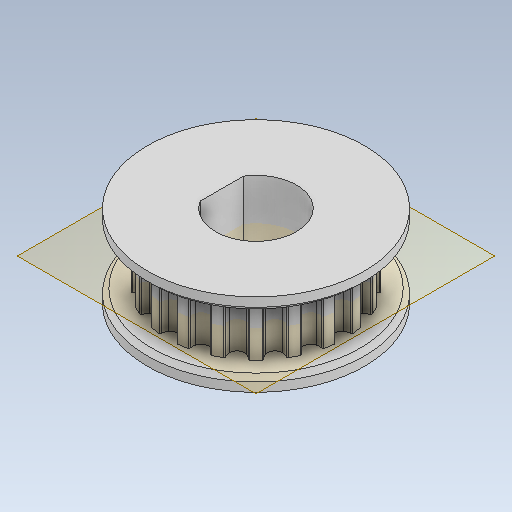
# Autodesk Inventor part: HTD-3M_20-Zähne
Saved by Autodesk Inventor 2026.4 (Build 304435030, 435C)
## iProperties
Created: 2026-11-19
Part Number: HTD-3M_20-Zähne
Material: Generisch
Document SubType Name: Modeling
Designer: weira
Density: 1 g/cm^3
Appearance: Vorgabe
Author: weira
Autodesk Inventor part; units mm, degrees
ref_plane "YZ Plane" through (0, 0, 0) normal (1, 0, 0) x (0, 1, 0)
ref_plane "XZ Plane" through (0, 0, 0) normal (0, 1, 0) x (-1, 0, 0)
sketch "Skizze1" plane through (0, 0, 0) normal (0, 0, 1) x (1, 0, 0)
  circle A0 centre (0, 0) radius 9.5511 construction
  line L0 (-5.6581, 20.033) -> (2.8903, 20.033)
  line L1 (2.8903, 20.033) -> (2.8903, 11.5277)
  line L2 (2.8903, 11.5277) -> (-5.6581, 11.5277)
  line L3 (-5.6581, 11.5277) -> (-5.6581, 20.033)
  circle A1 centre (0, 0) radius 8.6811 construction
  circle A2 centre (0, 0) radius 9.8211
  arc A3 (0.7095, 9.0476) -> (0.9041, 9.6681) centre (-0.61, 9.8021) ccw
  arc A4 (1.0279, 9.7672) -> (0.9041, 9.6681) centre (1.0264, 9.6422) ccw
  line L4 (0, 8.6811) -> (0, 7.1512) construction
  arc A5 (-0.9041, 9.6681) -> (-0.7095, 9.0476) centre (0.61, 9.8021) ccw
  arc A6 (-0.9041, 9.6681) -> (-1.0279, 9.7672) centre (-1.0264, 9.6422) ccw
  arc A7 (-0.7095, 9.0476) -> (0.7095, 9.0476) centre (0, 9.5511) ccw
  arc A8 (-2.0407, 9.6068) -> (-2.1278, 9.4743) centre (-2.0035, 9.4874) ccw
  arc A9 (-3.8474, 8.9155) -> (-3.9958, 8.9715) centre (-3.9557, 8.8531) ccw
  arc A10 (-2.1211, 8.824) -> (-2.1278, 9.4743) centre (-3.6092, 9.1339) ccw
  arc A11 (-3.8474, 8.9155) -> (-3.4706, 8.3855) centre (-2.4489, 9.5109) ccw
  arc A12 (-3.4706, 8.3855) -> (-2.1211, 8.824) centre (-2.9515, 9.0836) ccw
  arc A13 (-4.9094, 8.506) -> (-4.9513, 8.353) centre (-4.8372, 8.404) ccw
  arc A14 (-6.4142, 7.2902) -> (-6.5726, 7.2976) centre (-6.4979, 7.1974) ccw
  arc A15 (-4.744, 7.7367) -> (-4.9513, 8.353) centre (-6.2551, 7.5715) ccw
  arc A16 (-6.4142, 7.2902) -> (-5.892, 6.9026) centre (-5.2681, 8.2886) ccw
  arc A17 (-5.892, 6.9026) -> (-4.744, 7.7367) centre (-5.614, 7.727) ccw
  arc A18 (-7.2976, 6.5726) -> (-7.2902, 6.4142) centre (-7.1974, 6.4979) ccw
  arc A19 (-8.353, 4.9513) -> (-8.506, 4.9094) centre (-8.404, 4.8372) ccw
  arc A20 (-6.9026, 5.892) -> (-7.2902, 6.4142) centre (-8.2886, 5.2681) ccw
  arc A21 (-8.353, 4.9513) -> (-7.7367, 4.744) centre (-7.5715, 6.2551) ccw
  arc A22 (-7.7367, 4.744) -> (-6.9026, 5.892) centre (-7.727, 5.614) ccw
  arc A23 (-8.9715, 3.9958) -> (-8.9155, 3.8474) centre (-8.8531, 3.9557) ccw
  arc A24 (-9.4743, 2.1278) -> (-9.6068, 2.0407) centre (-9.4874, 2.0035) ccw
  arc A25 (-8.3855, 3.4706) -> (-8.9155, 3.8474) centre (-9.5109, 2.4489) ccw
  arc A26 (-9.4743, 2.1278) -> (-8.824, 2.1211) centre (-9.1339, 3.6092) ccw
  arc A27 (-8.824, 2.1211) -> (-8.3855, 3.4706) centre (-9.0836, 2.9515) ccw
  arc A28 (-9.7672, 1.0279) -> (-9.6681, 0.9041) centre (-9.6422, 1.0264) ccw
  arc A29 (-9.6681, -0.9041) -> (-9.7672, -1.0279) centre (-9.6422, -1.0264) ccw
  arc A30 (-9.0476, 0.7095) -> (-9.6681, 0.9041) centre (-9.8021, -0.61) ccw
  arc A31 (-9.6681, -0.9041) -> (-9.0476, -0.7095) centre (-9.8021, 0.61) ccw
  arc A32 (-9.0476, -0.7095) -> (-9.0476, 0.7095) centre (-9.5511, 0) ccw
  arc A33 (-9.6068, -2.0407) -> (-9.4743, -2.1278) centre (-9.4874, -2.0035) ccw
  arc A34 (-8.9155, -3.8474) -> (-8.9715, -3.9958) centre (-8.8531, -3.9557) ccw
  arc A35 (-8.824, -2.1211) -> (-9.4743, -2.1278) centre (-9.1339, -3.6092) ccw
  arc A36 (-8.9155, -3.8474) -> (-8.3855, -3.4706) centre (-9.5109, -2.4489) ccw
  arc A37 (-8.3855, -3.4706) -> (-8.824, -2.1211) centre (-9.0836, -2.9515) ccw
  arc A38 (-8.506, -4.9094) -> (-8.353, -4.9513) centre (-8.404, -4.8372) ccw
  arc A39 (-7.2902, -6.4142) -> (-7.2976, -6.5726) centre (-7.1974, -6.4979) ccw
  arc A40 (-7.7367, -4.744) -> (-8.353, -4.9513) centre (-7.5715, -6.2551) ccw
  arc A41 (-7.2902, -6.4142) -> (-6.9026, -5.892) centre (-8.2886, -5.2681) ccw
  arc A42 (-6.9026, -5.892) -> (-7.7367, -4.744) centre (-7.727, -5.614) ccw
  arc A43 (-6.5726, -7.2976) -> (-6.4142, -7.2902) centre (-6.4979, -7.1974) ccw
  arc A44 (-4.9513, -8.353) -> (-4.9094, -8.506) centre (-4.8372, -8.404) ccw
  arc A45 (-5.892, -6.9026) -> (-6.4142, -7.2902) centre (-5.2681, -8.2886) ccw
  arc A46 (-4.9513, -8.353) -> (-4.744, -7.7367) centre (-6.2551, -7.5715) ccw
  arc A47 (-4.744, -7.7367) -> (-5.892, -6.9026) centre (-5.614, -7.727) ccw
  arc A48 (-3.9958, -8.9715) -> (-3.8474, -8.9155) centre (-3.9557, -8.8531) ccw
  arc A49 (-2.1278, -9.4743) -> (-2.0407, -9.6068) centre (-2.0035, -9.4874) ccw
  arc A50 (-3.4706, -8.3855) -> (-3.8474, -8.9155) centre (-2.4489, -9.5109) ccw
  arc A51 (-2.1278, -9.4743) -> (-2.1211, -8.824) centre (-3.6092, -9.1339) ccw
  arc A52 (-2.1211, -8.824) -> (-3.4706, -8.3855) centre (-2.9515, -9.0836) ccw
  arc A53 (-1.0279, -9.7672) -> (-0.9041, -9.6681) centre (-1.0264, -9.6422) ccw
  arc A54 (0.9041, -9.6681) -> (1.0279, -9.7672) centre (1.0264, -9.6422) ccw
  arc A55 (-0.7095, -9.0476) -> (-0.9041, -9.6681) centre (0.61, -9.8021) ccw
  arc A56 (0.9041, -9.6681) -> (0.7095, -9.0476) centre (-0.61, -9.8021) ccw
  arc A57 (0.7095, -9.0476) -> (-0.7095, -9.0476) centre (0, -9.5511) ccw
  arc A58 (2.0407, -9.6068) -> (2.1278, -9.4743) centre (2.0035, -9.4874) ccw
  arc A59 (3.8474, -8.9155) -> (3.9958, -8.9715) centre (3.9557, -8.8531) ccw
  arc A60 (2.1211, -8.824) -> (2.1278, -9.4743) centre (3.6092, -9.1339) ccw
  arc A61 (3.8474, -8.9155) -> (3.4706, -8.3855) centre (2.4489, -9.5109) ccw
  arc A62 (3.4706, -8.3855) -> (2.1211, -8.824) centre (2.9515, -9.0836) ccw
  arc A63 (4.9094, -8.506) -> (4.9513, -8.353) centre (4.8372, -8.404) ccw
  arc A64 (6.4142, -7.2902) -> (6.5726, -7.2976) centre (6.4979, -7.1974) ccw
  arc A65 (4.744, -7.7367) -> (4.9513, -8.353) centre (6.2551, -7.5715) ccw
  arc A66 (6.4142, -7.2902) -> (5.892, -6.9026) centre (5.2681, -8.2886) ccw
  arc A67 (5.892, -6.9026) -> (4.744, -7.7367) centre (5.614, -7.727) ccw
  arc A68 (7.2976, -6.5726) -> (7.2902, -6.4142) centre (7.1974, -6.4979) ccw
  arc A69 (8.353, -4.9513) -> (8.506, -4.9094) centre (8.404, -4.8372) ccw
  arc A70 (6.9026, -5.892) -> (7.2902, -6.4142) centre (8.2886, -5.2681) ccw
  arc A71 (8.353, -4.9513) -> (7.7367, -4.744) centre (7.5715, -6.2551) ccw
  arc A72 (7.7367, -4.744) -> (6.9026, -5.892) centre (7.727, -5.614) ccw
  arc A73 (8.9715, -3.9958) -> (8.9155, -3.8474) centre (8.8531, -3.9557) ccw
  arc A74 (9.4743, -2.1278) -> (9.6068, -2.0407) centre (9.4874, -2.0035) ccw
  arc A75 (8.3855, -3.4706) -> (8.9155, -3.8474) centre (9.5109, -2.4489) ccw
  arc A76 (9.4743, -2.1278) -> (8.824, -2.1211) centre (9.1339, -3.6092) ccw
  arc A77 (8.824, -2.1211) -> (8.3855, -3.4706) centre (9.0836, -2.9515) ccw
  arc A78 (9.7672, -1.0279) -> (9.6681, -0.9041) centre (9.6422, -1.0264) ccw
  arc A79 (9.6681, 0.9041) -> (9.7672, 1.0279) centre (9.6422, 1.0264) ccw
  arc A80 (9.0476, -0.7095) -> (9.6681, -0.9041) centre (9.8021, 0.61) ccw
  arc A81 (9.6681, 0.9041) -> (9.0476, 0.7095) centre (9.8021, -0.61) ccw
  arc A82 (9.0476, 0.7095) -> (9.0476, -0.7095) centre (9.5511, 0) ccw
  arc A83 (9.6068, 2.0407) -> (9.4743, 2.1278) centre (9.4874, 2.0035) ccw
  arc A84 (8.9155, 3.8474) -> (8.9715, 3.9958) centre (8.8531, 3.9557) ccw
  arc A85 (8.824, 2.1211) -> (9.4743, 2.1278) centre (9.1339, 3.6092) ccw
  arc A86 (8.9155, 3.8474) -> (8.3855, 3.4706) centre (9.5109, 2.4489) ccw
  arc A87 (8.3855, 3.4706) -> (8.824, 2.1211) centre (9.0836, 2.9515) ccw
  arc A88 (8.506, 4.9094) -> (8.353, 4.9513) centre (8.404, 4.8372) ccw
  arc A89 (7.2902, 6.4142) -> (7.2976, 6.5726) centre (7.1974, 6.4979) ccw
  arc A90 (7.7367, 4.744) -> (8.353, 4.9513) centre (7.5715, 6.2551) ccw
  arc A91 (7.2902, 6.4142) -> (6.9026, 5.892) centre (8.2886, 5.2681) ccw
  arc A92 (6.9026, 5.892) -> (7.7367, 4.744) centre (7.727, 5.614) ccw
  arc A93 (6.5726, 7.2976) -> (6.4142, 7.2902) centre (6.4979, 7.1974) ccw
  arc A94 (4.9513, 8.353) -> (4.9094, 8.506) centre (4.8372, 8.404) ccw
  arc A95 (5.892, 6.9026) -> (6.4142, 7.2902) centre (5.2681, 8.2886) ccw
  arc A96 (4.9513, 8.353) -> (4.744, 7.7367) centre (6.2551, 7.5715) ccw
  arc A97 (4.744, 7.7367) -> (5.892, 6.9026) centre (5.614, 7.727) ccw
  arc A98 (3.9958, 8.9715) -> (3.8474, 8.9155) centre (3.9557, 8.8531) ccw
  arc A99 (2.1278, 9.4743) -> (2.0407, 9.6068) centre (2.0035, 9.4874) ccw
  arc A100 (3.4706, 8.3855) -> (3.8474, 8.9155) centre (2.4489, 9.5109) ccw
  arc A101 (2.1278, 9.4743) -> (2.1211, 8.824) centre (3.6092, 9.1339) ccw
  arc A102 (2.1211, 8.824) -> (3.4706, 8.3855) centre (2.9515, 9.0836) ccw
  circle A103 centre (0, 0) radius 12.0811
  point P0 (-2.6826, 8.2562)
  point P1 (-5.1026, 7.0232)
  point P2 (-7.0232, 5.1026)
  point P3 (-8.2562, 2.6826)
  point P4 (-8.6811, 0)
  point P5 (-8.2562, -2.6826)
  point P6 (-7.0232, -5.1026)
  point P7 (-5.1026, -7.0232)
  point P8 (-2.6826, -8.2562)
  point P9 (0, -8.6811)
  point P10 (2.6826, -8.2562)
  point P11 (5.1026, -7.0232)
  point P12 (7.0232, -5.1026)
  point P13 (8.2562, -2.6826)
  point P14 (8.6811, 0)
  point P15 (8.2562, 2.6826)
  point P16 (7.0232, 5.1026)
  point P17 (5.1026, 7.0232)
  point P18 (2.6826, 8.2562)
  point P19 (-2.0407, 9.6068)
  point P20 (-3.9958, 8.9715)
  point P21 (-4.9094, 8.506)
  point P22 (-6.5726, 7.2976)
  point P23 (-8.506, 4.9094)
  point P24 (-9.6068, -2.0407)
  point P25 (-8.506, -4.9094)
  point P26 (-7.2976, -6.5726)
  point P27 (-2.0407, -9.6068)
  point P28 (2.0407, -9.6068)
  point P29 (4.9094, -8.506)
  point P30 (6.5726, -7.2976)
  point P31 (9.6068, -2.0407)
  point P32 (9.6068, 2.0407)
  dimension "d166" = 19.1022
  dimension "d189" = 1.14
  dimension "d190" = 0.61
  dimension "d194" = 0.25
  dimension "d201" = 360
  dimension "d204" = 3.4
  constraints: 220 point on circle, 101 centre point, 5 coincident, 5 symmetric about line, 2 end point, 2 vertical alignment, 1 vertical, 353 other
  measures "d190" horizontal distance of A3.centre A7.centre
  measures "d194" diameter of A4
extrude "Extrusion1" add sketch "Skizze1" along normal mid plane 6.2 contours A79 A81 A82 A80 A78 A2 A74 A76 A77 A75 A73 A69 A71 A72 A70 A68 A64 A66 A67 A65 A63 A59 A61 A62 A60 A58 A54 A56 A57 A55 A53 A49 A51 A52 A50 A48 A44 A46 A47 A45 A43 A39 A41 A42 A40 A38 A34 A36 A37 A35 A33 A29 A31 A32 A30 A28 A24 A26 A27 A25 A23 A19 A21 A22 A20 A18 A14 A16 A17 A15 A13 A9 A11 A12 A10 A8 A6 A5 A7 A3 A4 A99 A101 A102 A100 A98 A94 A96 A97 A95 A93 A89 A91 A92 A90 A88 A84 A86 A87 A85 A83
sketch "Skizze3" plane through (0, 0, 3.1) normal (0, 0, 1) x (1, 0, 0)
  circle A0 centre (0, 0) radius 12.0811 projected
extrude "Extrusion4" add sketch "Skizze3" along normal blind 1.5
mirror "Spiegeln1" about plane through (0, 0, 0) normal (0, 0, 1) of "Extrusion4"
chamfer "Fasen1" distance 0.5 angle 45 2 edges at (-12.0811, 0, -3.1) (-12.0811, 0, 3.1)
sketch "Skizze6" plane through (0, 0, 4.6) normal (0, 0, 1) x (1, 0, 0)
  circle A0 centre (0, 0) radius 12.0811 projected
  arc A1 (3.2541, -35.227) -> (3.2541, -37.4631) centre (2.2541, -36.3451) ccw
  arc A2 (-1.5459, -38.7554) -> (-1.5459, -33.9347) centre (2.2541, -36.3451) ccw
  line L0 (-1.5459, -33.9347) -> (-1.5459, -38.7554)
  arc A3 (1, 1.118) -> (1, -1.118) centre (0, 0) ccw
  arc A4 (-3.8, -2.4104) -> (-3.8, 2.4104) centre (0, 0) ccw
  line L1 (-3.8, 2.4104) -> (-3.8, -2.4104)
  constraints: 8 point on circle, 4 centre point, 4 end point
extrude "Extrusion6" cut sketch "Skizze6" against normal through all contours L1 A4
